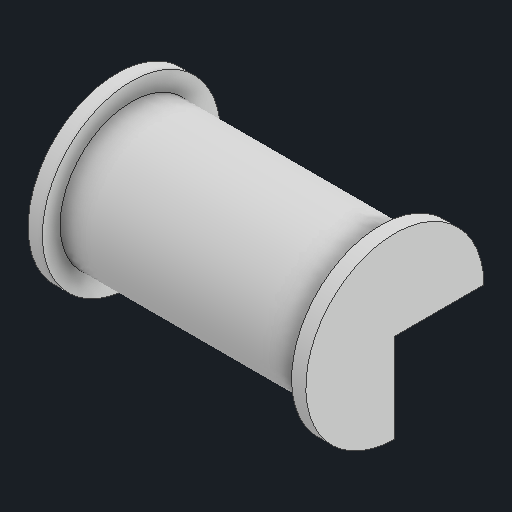
# Autodesk Inventor part: 7_4_2_devidoir
Saved by Autodesk Inventor 2026 (Build 300175000, 175)
## iProperties
Created: 2025-06-22
Part Number: 7_4_2_devidoir
Material: Generic
Document SubType Name: Modeling
Designer: remg9
Density: 1 g/cm^3
Appearance: Default
Author: remg9
Autodesk Inventor part; units mm, degrees
ref_plane "YZ Plane" through (0, 0, 0) normal (1, 0, 0) x (0, 1, 0)
ref_plane "XZ Plane" through (0, 0, 0) normal (0, 1, 0) x (-1, 0, 0)
ref_plane "XY Plane" through (0, 0, 0) normal (0, 0, 1) x (1, 0, 0)
sketch "Sketch1" plane through (0, 0, 0) normal (0, 0, 1) x (1, 0, 0)
  line L0 (0, 0) -> (60, 0)
  line L1 (60, 0) -> (60, 10)
  line L2 (60, 10) -> (0, 10)
  line L3 (0, 10) -> (0, 0)
  dimension "d0" = 60
  dimension "d1" = 10
  constraints: 8 end point, 2 parallel, 1 horizontal, 1 perpendicular
  measures "d0" distance of L1.end L2.end
  measures "d1" distance of L0.end L1.end
extrude "Extrusion1" add sketch "Sketch1" along normal blind 5
sketch "Sketch7" plane through (0, 0, 0) normal (-1, 0, 0) x (0, 0, 1)
  arc A0 (5, 0) -> (-15, 20) centre (5, 20) ccw
  line L0 (5, 20) -> (-15, 20)
  line L1 (5, 0) -> (5, 20)
  point P0 (0, 0)
  dimension "d23" = 20
  constraints: 4 end point, 2 point on circle, 1 centre point, 1 coincident, 1 horizontal, 1 perpendicular
  measures "d23" radius of A0
extrude "Extrusion7" add sketch "Sketch7" along normal blind 5 and the other way blind 65
sketch "Sketch8" plane through (-5, 0, 0) normal (-1, 0, 0) x (0, 0, 1)
  arc A0 (5, -5) -> (-20, 20) centre (5, 20) ccw
  line L0 (-20, 20) -> (5, 20)
  line L1 (5, 20) -> (5, -5)
  point P0 (0, 0)
  point P1 (5, 7.5)
  dimension "d28" = 25
  constraints: 4 end point, 2 point on circle, 1 centre point, 1 coincident, 1 horizontal, 1 midpoint, 1 vertical
  measures "d28" radius of A0
extrude "Extrusion8" add sketch "Sketch8" along normal blind 4
sketch "Sketch9" plane through (65, 0, 0) normal (1, 0, 0) x (0, 0, -1)
  arc A0 (20, 20) -> (-5, -5) centre (-5, 20) ccw
  line L0 (20, 20) -> (-5, 20)
  line L1 (-5, 20) -> (-5, -5)
  point P0 (0, 0)
  dimension "d31" = 25
  constraints: 4 end point, 2 point on circle, 1 centre point, 1 coincident, 1 horizontal, 1 perpendicular
  measures "d31" radius of A0
extrude "Extrusion9" add sketch "Sketch9" along normal blind 4
body "Solid1"
